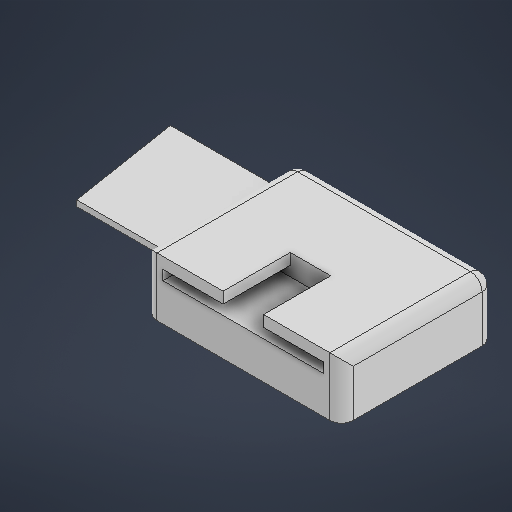
# Autodesk Inventor part: 2_10_plaque_servomotv2
Saved by Autodesk Inventor 2026 (Build 300175000, 175)
## iProperties
Created: 2025-06-22
Part Number: 2_10_plaque_servomotv2
Material: Générique
Document SubType Name: Modeling
Designer: Diogo
Density: 1 g/cm^3
Appearance: Par défaut
Author: Diogo
Autodesk Inventor part; units mm, degrees
ref_plane "YZ Plane" through (0, 0, 0) normal (1, 0, 0) x (0, 1, 0)
ref_plane "XZ Plane" through (0, 0, 0) normal (0, 1, 0) x (-1, 0, 0)
ref_plane "XY Plane" through (0, 0, 0) normal (0, 0, 1) x (1, 0, 0)
sketch "Esquisse1" plane through (0, 0, 0) normal (0, 1, 0) x (-1, 0, 0)
  line L0 (-18.7, 5) -> (-52.2, 5)
  line L1 (-52.2, 5) -> (-52.2, -21)
  line L2 (-52.2, -21) -> (3, -21)
  line L3 (3, -21) -> (3, -5)
  line L4 (-18.7, 5) -> (-18.7, -5)
  line L5 (-18.7, -5) -> (3, -5)
  point P0 (0, 0)
  dimension "d0" = 55.2
  dimension "d1" = 26
  dimension "d2" = 21.7
  dimension "d3" = 10
  dimension "d14" = 33.5
  constraints: 12 end point, 2 parallel, 1 horizontal, 1 perpendicular
  measures "d0" distance of L2.end L1.end
  measures "d1" distance of L1.end L0.end
  measures "d2" distance of L3.end L4.end
  measures "d3" distance of L0.start L4.end
  measures "d14" distance of L0.start L0.end
extrude "Extrusion1" add sketch "Esquisse1" along normal blind 10
sketch "Esquisse2" plane through (18.7, 0, 5) normal (0, 0, 1) x (1, 0, 0)
  line L0 (0, 0) -> (0, 10) construction
  line L1 (-31.8198, 0) -> (0, 0) construction
  line L2 (0, 0) -> (0, 4) construction
  line L3 (0, 4) -> (-31.8198, 4) construction
  line L4 (-31.8198, 4) -> (-31.8198, 0) construction
  line L5 (0, 4) -> (-21.7, 4)
  line L6 (-21.7, 4) -> (-21.7, 10)
  line L7 (-21.7, 10) -> (0, 10)
  line L8 (0, 10) -> (0, 4)
  dimension "d6" = 4
  constraints: 16 end point, 4 parallel, 2 horizontal, 2 perpendicular, 1 point on line
  measures "d6" distance of L2.end L1.end
extrude "Extrusion2" cut sketch "Esquisse2" against normal through all
sketch "Esquisse3" plane through (18.7, 0, 5) normal (0, 0, 1) x (1, 0, 0)
  line L0 (33.5, 0) -> (33.5, 10) construction
  line L1 (33.5, 0) -> (30.5, 0) construction
  line L2 (30.5, 0) -> (30.5, 12.9922) construction
  line L3 (30.5, 12.9922) -> (33.5, 12.9922) construction
  line L4 (33.5, 12.9922) -> (33.5, 0) construction
  line L5 (0, 0) -> (0, 10) construction
  line L6 (0, 10) -> (34.1822, 10) construction
  line L7 (34.1822, 10) -> (34.1822, 8.1) construction
  line L8 (0, 8.1) -> (0, 10) construction
  line L9 (35.952, 8.1) -> (35.952, 6.4) construction
  line L10 (35.952, 6.4) -> (0, 6.4) construction
  line L11 (0, 6.4) -> (0, 8.1) construction
  line L12 (0, 0) -> (3, 0) construction
  line L13 (3, 0) -> (3, 16.6242) construction
  line L14 (3, 16.6242) -> (0, 16.6242) construction
  line L15 (0, 16.6242) -> (0, 0) construction
  line L16 (30.5, 8.1) -> (30.5, 6.4)
  line L17 (30.5, 6.4) -> (3, 6.4)
  line L18 (3, 6.4) -> (3, 8.1)
  line L19 (30.5, 8.1) -> (20.2, 8.1) construction
  line L20 (16.75, 8.1) -> (16.75, 13.245) construction
  line L21 (16.75, 13.245) -> (30.5, 13.245) construction
  line L22 (30.5, 13.245) -> (30.5, 8.1) construction
  line L23 (20.2, 8.1) -> (20.2, 10)
  line L24 (20.2, 10) -> (16.75, 10)
  line L25 (13.3, 8.1) -> (13.3, 10)
  line L26 (13.3, 10) -> (16.75, 10)
  line L27 (3, 8.1) -> (13.3, 8.1)
  line L28 (20.2, 8.1) -> (30.5, 8.1)
  line L29 (0, 8.1) -> (13.3, 8.1) construction
  line L30 (16.75, 8.1) -> (35.952, 8.1) construction
  line L31 (34.1822, 8.1) -> (20.2, 8.1) construction
  line L32 (13.3, 8.1) -> (0, 8.1) construction
  point P0 (-18.7, 0)
  dimension "d9" = 3
  dimension "d10" = 1.9
  dimension "d11" = 1.7
  dimension "d12" = 3
  dimension "d13" = 13.75
  dimension "d15" = 3.45
  dimension "d16" = 3.45
  constraints: 62 end point, 15 parallel, 8 horizontal, 8 perpendicular, 6 point on line
  measures "d9" distance of L2.end L3.end
  measures "d10" distance of L6.end L7.end
  measures "d11" distance of L9.start L9.end
  measures "d12" distance of L14.end L13.end
  measures "d13" distance of L20.end L21.end
  measures "d15" distance of L24.end L23.end
  measures "d16" distance of L25.end L26.end
extrude "Extrusion3" cut sketch "Esquisse3" against normal blind 11.45
sketch "Esquisse4" plane through (-3, 0, -21) normal (-1, 0, 0) x (0, 0, 1)
  line L0 (16, 4) -> (0, 4) projected
  line L1 (16, 0) -> (16, 4) projected
  line L2 (16, 1) -> (16, 4)
  line L3 (26, 0) -> (0, 0) construction
  line L4 (0, 0) -> (22.364, 0) construction
  line L5 (22.364, 0) -> (22.364, 1) construction
  line L6 (22.364, 1) -> (0, 1) construction
  line L7 (0, 1) -> (0, 0) construction
  line L8 (0, 4) -> (16, 1)
  line L9 (16, 1) -> (16, 0)
  line L10 (0, 4) -> (0, 0)
  point P0 (21, 0)
  point P1 (16, 1)
  dimension "d22" = 1
  constraints: 16 end point, 3 collinear, 2 parallel, 1 horizontal, 1 perpendicular, 1 point on line
  measures "d22" distance of L5.end L4.end
extrude "Extrusion4" cut sketch "Esquisse4" against normal up to surface (21.7 mm away)
fillet "Congé1" radius 2 7 edges at (52.2, 5, -21) (52.2, 5, 5) (18.7, 5, 5) (18.7, 7, -21) (35.45, 10, -21) (18.7, 10, -8) (52.2, 10, -8)
